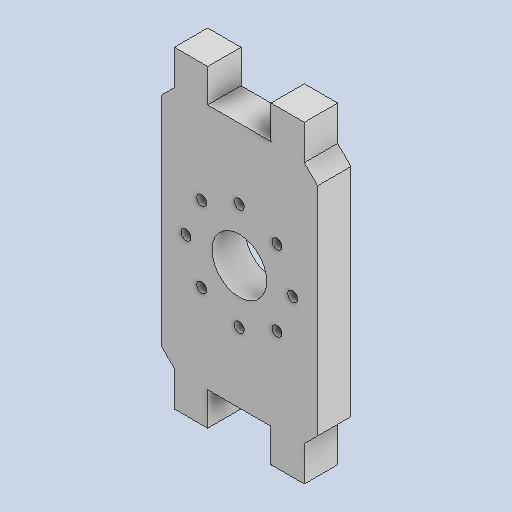
# Autodesk Inventor part: Pelv2
Saved by Autodesk Inventor 2025.2 (Build 292293000, 293)
## iProperties
Created: 2025-06-22
Part Number: Pelv2
Material: Generic
Document SubType Name: Modeling
Designer: ricoa
Density: 1 g/cm^3
Appearance: Default
Author: ricoa
Autodesk Inventor part; units mm, degrees
ref_plane "YZ Plane" through (0, 0, 0) normal (1, 0, 0) x (0, 1, 0)
ref_plane "XZ Plane" through (0, 0, 0) normal (0, 1, 0) x (-1, 0, 0)
ref_plane "XY Plane" through (0, 0, 0) normal (0, 0, 1) x (1, 0, 0)
sketch "Sketch1" plane through (0, 0, 0) normal (0, 0, 1) x (1, 0, 0)
  line L0 (21.5, -1) -> (21.5, -1)
  line L1 (21.5, -1) -> (21.5, -33.5)
  line L2 (-2, -33.5) -> (-2, -1)
  line L3 (-2, -1) -> (-2, -1)
  line L4 (0, 1) -> (0, 5)
  line L5 (19.5, 6.25) -> (14.5, 6.25)
  line L6 (14.5, 6.25) -> (14.5, 1.25)
  line L7 (14.5, 1.25) -> (5, 1.25)
  line L8 (5, 1.25) -> (5, 6.25)
  line L9 (5, 6.25) -> (0, 6.25)
  line L10 (0, 6.25) -> (0, 1.25)
  line L11 (19.5, 1) -> (21.5, -1)
  line L12 (0, 1) -> (-2, -1)
  line L13 (21.5, -17.25) -> (-2, -17.25) construction
  line L14 (21.5, -33.5) -> (21.5, -33.5)
  line L15 (-2, -33.5) -> (-2, -33.5)
  line L16 (9.75, -17.25) -> (9.75, 1.25)
  line L17 (19.5, 6.25) -> (19.5, 1)
  line L18 (21.5, -33.5) -> (21.5, -33.5)
  line L19 (-2, -33.5) -> (-2, -33.5)
  line L20 (0, -35.5) -> (0, -39.5)
  line L21 (19.5, -40.75) -> (14.5, -40.75)
  line L22 (14.5, -40.75) -> (14.5, -35.75)
  line L23 (14.5, -35.75) -> (5, -35.75)
  line L24 (5, -35.75) -> (5, -40.75)
  line L25 (5, -40.75) -> (0, -40.75)
  line L26 (0, -40.75) -> (0, -35.75)
  line L27 (19.5, -35.5) -> (21.5, -33.5)
  line L28 (0, -35.5) -> (-2, -33.5)
  line L29 (19.5, -40.75) -> (19.5, -35.5)
  point P0 (-2, -1)
  point P1 (9.75, -35.75)
  point P2 (0, 4.5594)
  point P3 (0, -39.0595)
  dimension "d10" = 5
  dimension "d15" = 18.5
  constraints: 60 end point, 19 symmetric about line, 11 point on line, 4 midpoint, 2 perpendicular, 1 vertical
  measures "d10" distance of L5.end L6.end
  measures "d15" distance of L16.start L16.end
extrude "Extrusion1" add sketch "Sketch1" along normal blind 5
sketch "Sketch2" plane through (0, 0, 0) normal (0, 0, -1) x (-1, 0, 0)
  line L0 (-14.5, 0) -> (-5, 0) projected
  line L1 (-9.75, 0) -> (-9.75, -34.5) construction
  line L2 (-5, -34.5) -> (-14.5, -34.5) projected
  line L3 (0, 6.25) -> (0, 1) projected
  line L4 (0, 3.625) -> (-19.5, -17.25) construction
  line L5 (-19.5, -39.5) -> (-19.5, 5) projected
  circle A0 centre (-9.75, -17.25) radius 9.75 projected
  circle A1 centre (-9.75, -17.25) radius 1 projected
  circle A2 centre (-15.4069, -11.5931) radius 0.75 projected
  circle A3 centre (-17.75, -17.25) radius 0.75 projected
  circle A4 centre (-15.4069, -22.9069) radius 0.75 projected
  circle A5 centre (-9.75, -25.25) radius 0.75 projected
  circle A6 centre (-4.0931, -22.9069) radius 0.75 projected
  circle A7 centre (-1.75, -17.25) radius 0.75 projected
  circle A8 centre (-4.0931, -11.5931) radius 0.75 projected
  circle A9 centre (-9.75, -9.25) radius 0.75 projected
  circle A10 centre (-9.75, -17.25) radius 4.1
  point P0 (0, 0)
  point P1 (0, 5)
  point P2 (0, -39.5)
  dimension "d16" = 8.2
  constraints: 4 end point, 4 midpoint, 1 centre point, 1 coincident, 1 horizontal alignment
  measures "d16" diameter of A10
extrude "Extrusion2" cut sketch "Sketch2" against normal blind 5 contours A1 | A2 | A3 | A4 | A5 | A6 | A7 | A8 | A9 | A10
body "Solid1"
